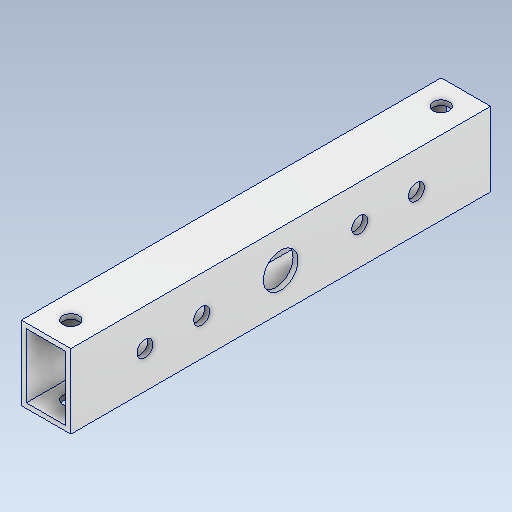
# Autodesk Inventor part: alsp_10_15_85_1
Saved by Autodesk Inventor 2027.1 (Build 311270010, 270A)
## iProperties
Created: 2026-10-09
Part Number: alsp_10_15_85_1
Material: アルミニウム 6061
Document SubType Name: Modeling
Designer: ug_nd
Density: 2.7 g/cm^3
Appearance: アルミニウム - フラット
Author: ug_nd
Autodesk Inventor part; units mm, degrees
ref_plane "YZ Plane" through (0, 0, 0) normal (1, 0, 0) x (0, 1, 0)
ref_plane "XZ Plane" through (0, 0, 0) normal (0, 1, 0) x (-1, 0, 0)
ref_plane "XY Plane" through (0, 0, 0) normal (0, 0, 1) x (1, 0, 0)
sketch "スケッチ1" plane through (0, 0, 0) normal (0, 0, 1) x (1, 0, 0)
  line L0 (-5, -7.5) -> (5, -7.5)
  line L1 (5, -7.5) -> (5, 7.5)
  line L2 (5, 7.5) -> (-5, 7.5)
  line L3 (-5, 7.5) -> (-5, -7.5)
  line L4 (-5, -7.5) -> (5, 7.5) construction
  line L5 (5, -7.5) -> (-5, 7.5) construction
  line L6 (-4, -6.5) -> (4, -6.5)
  line L7 (4, -6.5) -> (4, 6.5)
  line L8 (4, 6.5) -> (-4, 6.5)
  line L9 (-4, 6.5) -> (-4, -6.5)
  line L10 (-4, -6.5) -> (4, 6.5) construction
  line L11 (4, -6.5) -> (-4, 6.5) construction
  point P0 (0, 0)
  dimension "d0" = 10
  dimension "d1" = 15
  dimension "d2" = 1
  dimension "d3" = 1
  constraints: 24 end point, 4 midpoint, 4 parallel, 2 horizontal, 2 perpendicular
  measures "d0" distance of L1.end L2.end
  measures "d1" distance of L2.end L0.start
  measures "d2" distance between parallel lines of L8 L2
  measures "d3" distance between parallel lines of L3 L9
extrude "押し出し1" add sketch "スケッチ1" along normal mid plane 85
sketch "スケッチ2" plane through (5, -7.5, 42.5) normal (1, 0, 0) x (0, 0, -1)
  circle A0 centre (42.5, 7.5) radius 3.5
  line L0 (42.5, -3) -> (42.5, 18) construction
  line L1 (102, 7.5) -> (-17, 7.5) construction
  circle A1 centre (15, 7.5) radius 1.6
  circle A2 centre (26.5, 7.5) radius 1.6
  circle A3 centre (70, 7.5) radius 1.6
  circle A4 centre (58.5, 7.5) radius 1.6
  dimension "d6" = 7
  dimension "d16" = 55
  dimension "d17" = 3.2
  dimension "d18" = 32
  constraints: 5 centre point, 2 point on line, 2 symmetric about line, 1 coincident, 1 equal radius, 2 other
  measures "d6" diameter of A0
  measures "d16" distance of A3.centre A1.centre
  measures "d17" diameter of A3
  measures "d18" distance of A4.centre A2.centre
extrude "押し出し2" cut sketch "スケッチ2" against normal through all
sketch "スケッチ3" plane through (-5, -7.5, 42.5) normal (-1, 0, 0) x (0, 0, 1)
  circle A0 centre (-42.5, 7.5) radius 5
  dimension "d9" = 10
  constraints: 1 centre point, 1 coincident
  measures "d9" diameter of A0
extrude "押し出し3" cut sketch "スケッチ3" against normal up to surface (1 mm away)
sketch "スケッチ4" plane through (-5, 7.5, 42.5) normal (0, 1, 0) x (1, 0, 0)
  line L0 (5, 102) -> (5, -17) construction
  line L1 (-2, 42.5) -> (12, 42.5) construction
  circle A0 centre (5, 80) radius 1.6
  circle A1 centre (5, 5) radius 1.6
  point P0 (5, 42.5)
  dimension "d12" = 75
  dimension "d13" = 3.2
  constraints: 2 centre point, 1 point on line, 1 symmetric about line, 1 other
  measures "d12" distance of A1.centre A0.centre
  measures "d13" diameter of A0
extrude "押し出し4" cut sketch "スケッチ4" against normal through all
